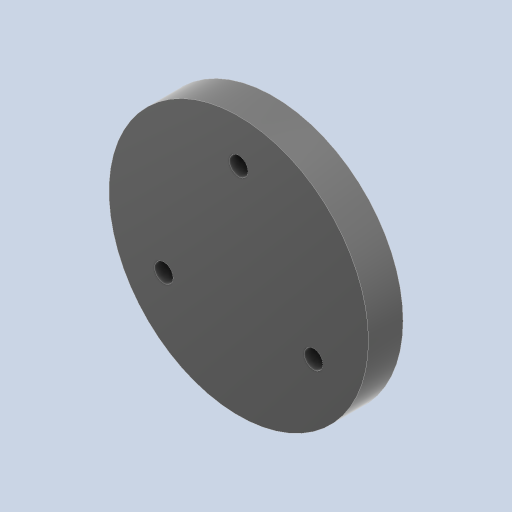
# Autodesk Inventor part: Espaçador roda
Saved by Autodesk Inventor 2024.3 (Build 283343000, 343)
## iProperties
Created: 2025-01-03
Part Number: Espaçador roda
Material: ABS plástico
Document SubType Name: Modeling
Designer: Cliente
Density: 0.908718 g/cm^3
Appearance: Suave - Preto
Mass: 20.238 g
Surface Area: 73.9991 cm^2
Volume: 22.2709 cm^3
Author: Cliente
Autodesk Inventor part; units mm, degrees
ref_plane "YZ Plane" through (0, 0, 0) normal (1, 0, 0) x (0, 1, 0)
ref_plane "XZ Plane" through (0, 0, 0) normal (0, 1, 0) x (-1, 0, 0)
ref_plane "XY Plane" through (0, 0, 0) normal (0, 0, 1) x (1, 0, 0)
sketch "Esboço1" plane through (0, 0, 0) normal (0, 0, 1) x (1, 0, 0)
  circle A0 centre (0, 0) radius 30
  line L0 (0, 0) -> (0, 20)
  circle A1 centre (0, 20) radius 2.15
  circle A2 centre (-17.3205, -10) radius 2.15
  circle A3 centre (17.3205, -10) radius 2.15
  dimension "d0" = 60
  dimension "d1" = 20
  dimension "d2" = 4.3
  dimension "d5" = 360
  constraints: 4 centre point, 2 coincident, 2 end point, 1 vertical, 7 other
  measures "d0" diameter of A0
  measures "d1" distance of L0.start L0.end
  measures "d2" diameter of A1
extrude "Extrusão1" add sketch "Esboço1" along normal mid plane 8
